210102_P01_WALL-PANEL-ASSY-SIDE-LOWER-RH_CAD (Autodesk Fusion 360 design; units mm, degrees)
part number: 2026-11-01-01-12-47-745
description: WALL - PANEL FRAME - SIDE LOWER - RH | Vách phải - khung dưới | P01
part number: 211102
description: WALL - SKIN - SIDE LOWER - RH | Vách phải - tấm ốp alu dưới | P01
part number: 211302
description: WALL - CAVITY FILL - SIDE LOWER - RH | Vách phải - bông PET dưới | P01
part number: 211502
description: HARDWARE - STOP WASHER - Ø10.5 X Ø20 X 1.5 - AL | Long đen chặn nhôm | P01
part number: 831002
description: HARDWARE - RIVET NUT - M6 - SHEREX CAH3-610-4.2 | Tán rút M6 | P01
part number: 838003
description: HARDWARE - LOCATING SPIGOT - M6 X Ø8 - STAINLESS | Chốt định vị Ø8 | P01
part number: 831001
Autodesk Fusion 360 part; units mm, degrees
(part 1 of 2)
ref_plane "WorkPlane1" through (0, 0, 112.26) normal (0, 0, 1) x (1, 0, 0) in component "211102 WALL - PANEL FRAME - SIDE LOWER - RH"
sketch "SKETCH - RAIL - BOTTOM TUBE" plane through (0, 0, 112.26) normal (0, 0, 1) x (1, 0, 0) in component "211102 WALL - PANEL FRAME - SIDE LOWER - RH"
  line L0 (1204, -642.74) -> (1244, -642.74)
  line L1 (1244, -642.74) -> (1244, 847)
  line L2 (1244, 847) -> (1204, 847)
  line L3 (1204, 847) -> (1204, -642.74)
  dimension "d167" = 40
  dimension "d168" = 1489.74
  dimension "d169" = 1204
  dimension "d170" = 642.74
  constraint horizontal L0
  constraint vertical L1
  constraint horizontal L2
  constraint vertical L3
  measures "d167" horizontal distance of L0.start L0.end
  measures "d168" vertical distance of L0.start L2.end
  measures "d169" horizontal distance of origin L0.start
  measures "d170" vertical distance of origin L0.start
extrude "EXTRUDE - RAIL - BOTTOM TUBE" add sketch "SKETCH - RAIL - BOTTOM TUBE" along normal blind 20 makes body 1 in component "211102 WALL - PANEL FRAME - SIDE LOWER - RH"
ref_plane "WorkPlane2" through (0, 0, 113.46) normal (0, 0, 1) x (1, 0, 0) in component "211102 WALL - PANEL FRAME - SIDE LOWER - RH"
sketch "SKETCH - RAIL - BOTTOM BORE" plane through (0, 0, 113.46) normal (0, 0, 1) x (1, 0, 0) in component "211102 WALL - PANEL FRAME - SIDE LOWER - RH"
  line L0 (1205.2, -642.74) -> (1242.8, -642.74)
  line L1 (1242.8, -642.74) -> (1242.8, 847)
  line L2 (1242.8, 847) -> (1205.2, 847)
  line L3 (1205.2, 847) -> (1205.2, -642.74)
  dimension "d175" = 37.6
  dimension "d176" = 1489.74
  dimension "d177" = 1205.2
  dimension "d178" = 642.74
  constraint horizontal L0
  constraint vertical L1
  constraint horizontal L2
  constraint vertical L3
  measures "d175" horizontal distance of L0.start L0.end
  measures "d176" vertical distance of L0.start L2.end
  measures "d177" horizontal distance of origin L0.start
  measures "d178" vertical distance of origin L0.start
extrude "CUT - RAIL - BOTTOM BORE" cut sketch "SKETCH - RAIL - BOTTOM BORE" along normal blind 17.6 bodies 1 in component "211102 WALL - PANEL FRAME - SIDE LOWER - RH"
ref_plane "WorkPlane3" through (0, 0, 1235) normal (0, 0, 1) x (1, 0, 0) in component "211102 WALL - PANEL FRAME - SIDE LOWER - RH"
sketch "SKETCH - RAIL - TOP TUBE" plane through (0, 0, 1235) normal (0, 0, 1) x (1, 0, 0) in component "211102 WALL - PANEL FRAME - SIDE LOWER - RH"
  line L0 (1204, -642.74) -> (1244, -642.74)
  line L1 (1244, -642.74) -> (1244, 847)
  line L2 (1244, 847) -> (1204, 847)
  line L3 (1204, 847) -> (1204, -642.74)
  dimension "d183" = 40
  dimension "d184" = 1489.74
  dimension "d185" = 1204
  dimension "d186" = 642.74
  constraint horizontal L0
  constraint vertical L1
  constraint horizontal L2
  constraint vertical L3
  measures "d183" horizontal distance of L0.start L0.end
  measures "d184" vertical distance of L0.start L2.end
  measures "d185" horizontal distance of origin L0.start
  measures "d186" vertical distance of origin L0.start
extrude "EXTRUDE - RAIL - TOP TUBE" add sketch "SKETCH - RAIL - TOP TUBE" along normal blind 20 separate body makes body 2 in component "211102 WALL - PANEL FRAME - SIDE LOWER - RH"
ref_plane "WorkPlane4" through (0, 0, 1236.2) normal (0, 0, 1) x (1, 0, 0) in component "211102 WALL - PANEL FRAME - SIDE LOWER - RH"
sketch "SKETCH - RAIL - TOP BORE" plane through (0, 0, 1236.2) normal (0, 0, 1) x (1, 0, 0) in component "211102 WALL - PANEL FRAME - SIDE LOWER - RH"
  line L0 (1205.2, -642.74) -> (1242.8, -642.74)
  line L1 (1242.8, -642.74) -> (1242.8, 847)
  line L2 (1242.8, 847) -> (1205.2, 847)
  line L3 (1205.2, 847) -> (1205.2, -642.74)
  dimension "d191" = 37.6
  dimension "d192" = 1489.74
  dimension "d193" = 1205.2
  dimension "d194" = 642.74
  constraint horizontal L0
  constraint vertical L1
  constraint horizontal L2
  constraint vertical L3
  measures "d191" horizontal distance of L0.start L0.end
  measures "d192" vertical distance of L0.start L2.end
  measures "d193" horizontal distance of origin L0.start
  measures "d194" vertical distance of origin L0.start
extrude "CUT - RAIL - TOP BORE" cut sketch "SKETCH - RAIL - TOP BORE" along normal blind 17.6 bodies 2 in component "211102 WALL - PANEL FRAME - SIDE LOWER - RH"
ref_plane "WorkPlane5" through (0, 0, 132.26) normal (0, 0, 1) x (1, 0, 0) in component "211102 WALL - PANEL FRAME - SIDE LOWER - RH"
sketch "SKETCH - STILE - FRONT TUBE" plane through (0, 0, 132.26) normal (0, 0, 1) x (1, 0, 0) in component "211102 WALL - PANEL FRAME - SIDE LOWER - RH"
  line L0 (1204, -642.74) -> (1244, -642.74)
  line L1 (1244, -642.74) -> (1244, -622.74)
  line L2 (1244, -622.74) -> (1204, -622.74)
  line L3 (1204, -622.74) -> (1204, -642.74)
  dimension "d199" = 40
  dimension "d200" = 20
  dimension "d201" = 1204
  dimension "d202" = 642.74
  constraint horizontal L0
  constraint vertical L1
  constraint horizontal L2
  constraint vertical L3
  measures "d199" horizontal distance of L0.start L0.end
  measures "d200" vertical distance of L0.start L2.end
  measures "d201" horizontal distance of origin L0.start
  measures "d202" vertical distance of origin L0.start
extrude "EXTRUDE - STILE - FRONT TUBE" add sketch "SKETCH - STILE - FRONT TUBE" along normal blind 1102.74 separate body makes body 3 in component "211102 WALL - PANEL FRAME - SIDE LOWER - RH"
ref_plane "WorkPlane6" through (0, 0, 132.26) normal (0, 0, 1) x (1, 0, 0) in component "211102 WALL - PANEL FRAME - SIDE LOWER - RH"
sketch "SKETCH - STILE - FRONT BORE" plane through (0, 0, 132.26) normal (0, 0, 1) x (1, 0, 0) in component "211102 WALL - PANEL FRAME - SIDE LOWER - RH"
  line L0 (1205.2, -641.54) -> (1242.8, -641.54)
  line L1 (1242.8, -641.54) -> (1242.8, -623.94)
  line L2 (1242.8, -623.94) -> (1205.2, -623.94)
  line L3 (1205.2, -623.94) -> (1205.2, -641.54)
  dimension "d207" = 37.6
  dimension "d208" = 17.6
  dimension "d209" = 1205.2
  dimension "d210" = 641.54
  constraint horizontal L0
  constraint vertical L1
  constraint horizontal L2
  constraint vertical L3
  measures "d207" horizontal distance of L0.start L0.end
  measures "d208" vertical distance of L0.start L2.end
  measures "d209" horizontal distance of origin L0.start
  measures "d210" vertical distance of origin L0.start
extrude "CUT - STILE - FRONT BORE" cut sketch "SKETCH - STILE - FRONT BORE" along normal blind 1102.74 bodies 3 in component "211102 WALL - PANEL FRAME - SIDE LOWER - RH"
ref_plane "WorkPlane7" through (0, 0, 132.26) normal (0, 0, 1) x (1, 0, 0) in component "211102 WALL - PANEL FRAME - SIDE LOWER - RH"
sketch "SKETCH - STILE - BACK TUBE" plane through (0, 0, 132.26) normal (0, 0, 1) x (1, 0, 0) in component "211102 WALL - PANEL FRAME - SIDE LOWER - RH"
  line L0 (1204, 807) -> (1244, 807)
  line L1 (1244, 807) -> (1244, 847)
  line L2 (1244, 847) -> (1204, 847)
  line L3 (1204, 847) -> (1204, 807)
  dimension "d215" = 40
  dimension "d216" = 40
  dimension "d217" = 1204
  dimension "d218" = 807
  constraint horizontal L0
  constraint vertical L1
  constraint horizontal L2
  constraint vertical L3
  measures "d215" horizontal distance of L0.start L0.end
  measures "d216" vertical distance of L0.start L2.end
  measures "d217" horizontal distance of origin L0.start
  measures "d218" vertical distance of origin L0.start
extrude "EXTRUDE - STILE - BACK TUBE" add sketch "SKETCH - STILE - BACK TUBE" along normal blind 1102.74 separate body makes body 4 in component "211102 WALL - PANEL FRAME - SIDE LOWER - RH"
ref_plane "WorkPlane8" through (0, 0, 132.26) normal (0, 0, 1) x (1, 0, 0) in component "211102 WALL - PANEL FRAME - SIDE LOWER - RH"
sketch "SKETCH - STILE - BACK BORE" plane through (0, 0, 132.26) normal (0, 0, 1) x (1, 0, 0) in component "211102 WALL - PANEL FRAME - SIDE LOWER - RH"
  line L0 (1205.2, 808.2) -> (1242.8, 808.2)
  line L1 (1242.8, 808.2) -> (1242.8, 845.8)
  line L2 (1242.8, 845.8) -> (1205.2, 845.8)
  line L3 (1205.2, 845.8) -> (1205.2, 808.2)
  dimension "d223" = 37.6
  dimension "d224" = 37.6
  dimension "d225" = 1205.2
  dimension "d226" = 808.2
  constraint horizontal L0
  constraint vertical L1
  constraint horizontal L2
  constraint vertical L3
  measures "d223" horizontal distance of L0.start L0.end
  measures "d224" vertical distance of L0.start L2.end
  measures "d225" horizontal distance of origin L0.start
  measures "d226" vertical distance of origin L0.start
extrude "CUT - STILE - BACK BORE" cut sketch "SKETCH - STILE - BACK BORE" along normal blind 1102.74 bodies 4 in component "211102 WALL - PANEL FRAME - SIDE LOWER - RH"
ref_plane "WorkPlane9" through (0, 0, 132.26) normal (0, 0, 1) x (1, 0, 0) in component "211102 WALL - PANEL FRAME - SIDE LOWER - RH"
sketch "SKETCH - STILE - MID 1 TUBE" plane through (0, 0, 132.26) normal (0, 0, 1) x (1, 0, 0) in component "211102 WALL - PANEL FRAME - SIDE LOWER - RH"
  line L0 (1204, -277.805) -> (1244, -277.805)
  line L1 (1244, -277.805) -> (1244, -257.805)
  line L2 (1244, -257.805) -> (1204, -257.805)
  line L3 (1204, -257.805) -> (1204, -277.805)
  dimension "d231" = 40
  dimension "d232" = 20
  dimension "d233" = 1204
  dimension "d234" = 277.805
  constraint horizontal L0
  constraint vertical L1
  constraint horizontal L2
  constraint vertical L3
  measures "d231" horizontal distance of L0.start L0.end
  measures "d232" vertical distance of L0.start L2.end
  measures "d233" horizontal distance of origin L0.start
  measures "d234" vertical distance of origin L0.start
extrude "EXTRUDE - STILE - MID 1 TUBE" add sketch "SKETCH - STILE - MID 1 TUBE" along normal blind 1102.74 separate body makes body 5 in component "211102 WALL - PANEL FRAME - SIDE LOWER - RH"
ref_plane "WorkPlane10" through (0, 0, 132.26) normal (0, 0, 1) x (1, 0, 0) in component "211102 WALL - PANEL FRAME - SIDE LOWER - RH"
sketch "SKETCH - STILE - MID 1 BORE" plane through (0, 0, 132.26) normal (0, 0, 1) x (1, 0, 0) in component "211102 WALL - PANEL FRAME - SIDE LOWER - RH"
  line L0 (1205, -276.805) -> (1243, -276.805)
  line L1 (1243, -276.805) -> (1243, -258.805)
  line L2 (1243, -258.805) -> (1205, -258.805)
  line L3 (1205, -258.805) -> (1205, -276.805)
  dimension "d239" = 38
  dimension "d240" = 18
  dimension "d241" = 1205
  dimension "d242" = 276.805
  constraint horizontal L0
  constraint vertical L1
  constraint horizontal L2
  constraint vertical L3
  measures "d239" horizontal distance of L0.start L0.end
  measures "d240" vertical distance of L0.start L2.end
  measures "d241" horizontal distance of origin L0.start
  measures "d242" vertical distance of origin L0.start
extrude "CUT - STILE - MID 1 BORE" cut sketch "SKETCH - STILE - MID 1 BORE" along normal blind 1102.74 bodies 5 in component "211102 WALL - PANEL FRAME - SIDE LOWER - RH"
pattern_linear "PATTERN - STILES - MID" count 3 spacing 364.935 along (0, 1, 0) of bodies 5 makes body 6 at (1230.6667, 107.13, 499.84) makes body 7 at (1230.6667, 472.065, 499.84) in component "211102 WALL - PANEL FRAME - SIDE LOWER - RH"
ref_plane "WorkPlane1" through (0, 0, 112.26) normal (0, 0, 1) x (1, 0, 0) in component "211302 WALL - SKIN - SIDE LOWER - RH"
sketch "SKETCH - SKIN PLATE" plane through (0, 0, 112.26) normal (0, 0, 1) x (1, 0, 0) in component "211302 WALL - SKIN - SIDE LOWER - RH"
  line L0 (1247, -642.74) -> (1250, -642.74)
  line L1 (1250, -642.74) -> (1250, 850)
  line L2 (1250, 850) -> (1247, 850)
  line L3 (1247, 850) -> (1247, -642.74)
  dimension "d251" = 3
  dimension "d252" = 1492.74
  dimension "d253" = 1247
  dimension "d254" = 642.74
  constraint horizontal L0
  constraint vertical L1
  constraint horizontal L2
  constraint vertical L3
  measures "d251" horizontal distance of L0.start L0.end
  measures "d252" vertical distance of L0.start L2.end
  measures "d253" horizontal distance of origin L0.start
  measures "d254" vertical distance of origin L0.start
extrude "EXTRUDE - SKIN PLATE" add sketch "SKETCH - SKIN PLATE" along normal blind 1142.74 separate body makes body 8 in component "211302 WALL - SKIN - SIDE LOWER - RH"
ref_plane "WorkPlane2" through (0, 0, 112.26) normal (0, 0, 1) x (1, 0, 0) in component "211302 WALL - SKIN - SIDE LOWER - RH"
sketch "SKETCH - SKIN BACK RETURN" plane through (0, 0, 112.26) normal (0, 0, 1) x (1, 0, 0) in component "211302 WALL - SKIN - SIDE LOWER - RH"
  line L0 (1204, 847) -> (1247, 847)
  line L1 (1247, 847) -> (1247, 850)
  line L2 (1247, 850) -> (1204, 850)
  line L3 (1204, 850) -> (1204, 847)
  dimension "d259" = 43
  dimension "d260" = 3
  dimension "d261" = 1204
  dimension "d262" = 847
  constraint horizontal L0
  constraint vertical L1
  constraint horizontal L2
  constraint vertical L3
  measures "d259" horizontal distance of L0.start L0.end
  measures "d260" vertical distance of L0.start L2.end
  measures "d261" horizontal distance of origin L0.start
  measures "d262" vertical distance of origin L0.start
extrude "JOIN - SKIN BACK RETURN" add sketch "SKETCH - SKIN BACK RETURN" along normal blind 1142.74 bodies 8 in component "211302 WALL - SKIN - SIDE LOWER - RH"
ref_plane "WorkPlane1" through (0, 0, 132.26) normal (0, 0, 1) x (1, 0, 0) in component "211502 WALL - CAVITY FILL - SIDE LOWER - RH"
sketch "SKETCH - FILL BAY 1" plane through (0, 0, 132.26) normal (0, 0, 1) x (1, 0, 0) in component "211502 WALL - CAVITY FILL - SIDE LOWER - RH"
  line L0 (1204, -622.74) -> (1244, -622.74)
  line L1 (1244, -622.74) -> (1244, -277.805)
  line L2 (1244, -277.805) -> (1204, -277.805)
  line L3 (1204, -277.805) -> (1204, -622.74)
  dimension "d267" = 40
  dimension "d268" = 344.935
  dimension "d269" = 1204
  dimension "d270" = 622.74
  constraint horizontal L0
  constraint vertical L1
  constraint horizontal L2
  constraint vertical L3
  measures "d267" horizontal distance of L0.start L0.end
  measures "d268" vertical distance of L0.start L2.end
  measures "d269" horizontal distance of origin L0.start
  measures "d270" vertical distance of origin L0.start
extrude "EXTRUDE - FILL BAY 1" add sketch "SKETCH - FILL BAY 1" along normal blind 1102.74 separate body makes body 9 in component "211502 WALL - CAVITY FILL - SIDE LOWER - RH"
pattern_linear "PATTERN - FILL BAYS" count 3 spacing 364.935 along (0, 1, 0) of bodies 9 makes body 10 at (1204, -27.8483, 499.84) makes body 11 at (1204, 337.0867, 499.84) in component "211502 WALL - CAVITY FILL - SIDE LOWER - RH"
ref_plane "WorkPlane2" through (0, 0, 132.26) normal (0, 0, 1) x (1, 0, 0) in component "211502 WALL - CAVITY FILL - SIDE LOWER - RH"
sketch "SKETCH - FILL BAY LAST" plane through (0, 0, 132.26) normal (0, 0, 1) x (1, 0, 0) in component "211502 WALL - CAVITY FILL - SIDE LOWER - RH"
  line L0 (1204, 472.065) -> (1244, 472.065)
  line L1 (1244, 472.065) -> (1244, 807)
  line L2 (1244, 807) -> (1204, 807)
  line L3 (1204, 807) -> (1204, 472.065)
  dimension "d279" = 40
  dimension "d280" = 334.935
  dimension "d281" = 1204
  dimension "d282" = 472.065
  constraint horizontal L0
  constraint vertical L1
  constraint horizontal L2
  constraint vertical L3
  measures "d279" horizontal distance of L0.start L0.end
  measures "d280" vertical distance of L0.start L2.end
  measures "d281" horizontal distance of origin L0.start
  measures "d282" vertical distance of origin L0.start
extrude "EXTRUDE - FILL BAY LAST" add sketch "SKETCH - FILL BAY LAST" along normal blind 1102.74 separate body makes body 12 in component "211502 WALL - CAVITY FILL - SIDE LOWER - RH"
ref_plane "WorkPlane3" through (0, 0, 132.26) normal (0, 0, 1) x (1, 0, 0) in component "211502 WALL - CAVITY FILL - SIDE LOWER - RH"
sketch "SKETCH - FILL POCKET BOTTOM BOLT 1" plane through (0, 0, 132.26) normal (0, 0, 1) x (1, 0, 0) in component "211502 WALL - CAVITY FILL - SIDE LOWER - RH"
  line L0 (1204, -452.74) -> (1244, -452.74)
  line L1 (1244, -452.74) -> (1244, -392.74)
  line L2 (1244, -392.74) -> (1204, -392.74)
  line L3 (1204, -392.74) -> (1204, -452.74)
  dimension "d287" = 40
  dimension "d288" = 60
  dimension "d289" = 1204
  dimension "d290" = 452.74
  constraint horizontal L0
  constraint vertical L1
  constraint horizontal L2
  constraint vertical L3
  measures "d287" horizontal distance of L0.start L0.end
  measures "d288" vertical distance of L0.start L2.end
  measures "d289" horizontal distance of origin L0.start
  measures "d290" vertical distance of origin L0.start
extrude "CUT - FILL POCKET BOTTOM BOLT 1" cut sketch "SKETCH - FILL POCKET BOTTOM BOLT 1" along normal blind 60 bodies 9 in component "211502 WALL - CAVITY FILL - SIDE LOWER - RH"
ref_plane "WorkPlane4" through (0, 0, 132.26) normal (0, 0, 1) x (1, 0, 0) in component "211502 WALL - CAVITY FILL - SIDE LOWER - RH"
sketch "SKETCH - FILL POCKET BOTTOM BOLT 2" plane through (0, 0, 132.26) normal (0, 0, 1) x (1, 0, 0) in component "211502 WALL - CAVITY FILL - SIDE LOWER - RH"
  line L0 (1204, -101.8267) -> (1244, -101.8267)
  line L1 (1244, -101.8267) -> (1244, -41.8267)
  line L2 (1244, -41.8267) -> (1204, -41.8267)
  line L3 (1204, -41.8267) -> (1204, -101.8267)
  dimension "d295" = 40
  dimension "d296" = 60
  dimension "d297" = 1204
  dimension "d298" = 101.8267
  constraint horizontal L0
  constraint vertical L1
  constraint horizontal L2
  constraint vertical L3
  measures "d295" horizontal distance of L0.start L0.end
  measures "d296" vertical distance of L0.start L2.end
  measures "d297" horizontal distance of origin L0.start
  measures "d298" vertical distance of origin L0.start
extrude "CUT - FILL POCKET BOTTOM BOLT 2" cut sketch "SKETCH - FILL POCKET BOTTOM BOLT 2" along normal blind 60 bodies 10 in component "211502 WALL - CAVITY FILL - SIDE LOWER - RH"
ref_plane "WorkPlane5" through (0, 0, 132.26) normal (0, 0, 1) x (1, 0, 0) in component "211502 WALL - CAVITY FILL - SIDE LOWER - RH"
sketch "SKETCH - FILL POCKET BOTTOM BOLT 3" plane through (0, 0, 132.26) normal (0, 0, 1) x (1, 0, 0) in component "211502 WALL - CAVITY FILL - SIDE LOWER - RH"
  line L0 (1204, 249.0867) -> (1244, 249.0867)
  line L1 (1244, 249.0867) -> (1244, 309.0867)
  line L2 (1244, 309.0867) -> (1204, 309.0867)
  line L3 (1204, 309.0867) -> (1204, 249.0867)
  dimension "d303" = 40
  dimension "d304" = 60
  dimension "d305" = 1204
  dimension "d306" = 249.0867
  constraint horizontal L0
  constraint vertical L1
  constraint horizontal L2
  constraint vertical L3
  measures "d303" horizontal distance of L0.start L0.end
  measures "d304" vertical distance of L0.start L2.end
  measures "d305" horizontal distance of origin L0.start
  measures "d306" vertical distance of origin L0.start
extrude "CUT - FILL POCKET BOTTOM BOLT 3" cut sketch "SKETCH - FILL POCKET BOTTOM BOLT 3" along normal blind 60 bodies 11 in component "211502 WALL - CAVITY FILL - SIDE LOWER - RH"
ref_plane "WorkPlane6" through (0, 0, 132.26) normal (0, 0, 1) x (1, 0, 0) in component "211502 WALL - CAVITY FILL - SIDE LOWER - RH"
sketch "SKETCH - FILL POCKET BOTTOM BOLT 4" plane through (0, 0, 132.26) normal (0, 0, 1) x (1, 0, 0) in component "211502 WALL - CAVITY FILL - SIDE LOWER - RH"
  line L0 (1204, 600) -> (1244, 600)
  line L1 (1244, 600) -> (1244, 660)
  line L2 (1244, 660) -> (1204, 660)
  line L3 (1204, 660) -> (1204, 600)
  dimension "d311" = 40
  dimension "d312" = 60
  dimension "d313" = 1204
  dimension "d314" = 600
  constraint horizontal L0
  constraint vertical L1
  constraint horizontal L2
  constraint vertical L3
  measures "d311" horizontal distance of L0.start L0.end
  measures "d312" vertical distance of L0.start L2.end
  measures "d313" horizontal distance of origin L0.start
  measures "d314" vertical distance of origin L0.start
extrude "CUT - FILL POCKET BOTTOM BOLT 4" cut sketch "SKETCH - FILL POCKET BOTTOM BOLT 4" along normal blind 60 bodies 12 in component "211502 WALL - CAVITY FILL - SIDE LOWER - RH"
ref_plane "WorkPlane7" through (0, 0, 302.26) normal (0, 0, 1) x (1, 0, 0) in component "211502 WALL - CAVITY FILL - SIDE LOWER - RH"
sketch "SKETCH - FILL POCKET DECOR BOLT 1" plane through (0, 0, 302.26) normal (0, 0, 1) x (1, 0, 0) in component "211502 WALL - CAVITY FILL - SIDE LOWER - RH"
  line L0 (1204, -622.74) -> (1244, -622.74)
  line L1 (1244, -622.74) -> (1244, -562.74)
  line L2 (1244, -562.74) -> (1204, -562.74)
  line L3 (1204, -562.74) -> (1204, -622.74)
  dimension "d319" = 40
  dimension "d320" = 60
  dimension "d321" = 1204
  dimension "d322" = 622.74
  constraint horizontal L0
  constraint vertical L1
  constraint horizontal L2
  constraint vertical L3
  measures "d319" horizontal distance of L0.start L0.end
  measures "d320" vertical distance of L0.start L2.end
  measures "d321" horizontal distance of origin L0.start
  measures "d322" vertical distance of origin L0.start
extrude "CUT - FILL POCKET DECOR BOLT 1" cut sketch "SKETCH - FILL POCKET DECOR BOLT 1" along normal blind 60 bodies 9 in component "211502 WALL - CAVITY FILL - SIDE LOWER - RH"
ref_plane "WorkPlane8" through (0, 0, 653.63) normal (0, 0, 1) x (1, 0, 0) in component "211502 WALL - CAVITY FILL - SIDE LOWER - RH"
sketch "SKETCH - FILL POCKET DECOR BOLT 2" plane through (0, 0, 653.63) normal (0, 0, 1) x (1, 0, 0) in component "211502 WALL - CAVITY FILL - SIDE LOWER - RH"
  line L0 (1204, -622.74) -> (1244, -622.74)
  line L1 (1244, -622.74) -> (1244, -562.74)
  line L2 (1244, -562.74) -> (1204, -562.74)
  line L3 (1204, -562.74) -> (1204, -622.74)
  dimension "d327" = 40
  dimension "d328" = 60
  dimension "d329" = 1204
  dimension "d330" = 622.74
  constraint horizontal L0
  constraint vertical L1
  constraint horizontal L2
  constraint vertical L3
  measures "d327" horizontal distance of L0.start L0.end
  measures "d328" vertical distance of L0.start L2.end
  measures "d329" horizontal distance of origin L0.start
  measures "d330" vertical distance of origin L0.start
extrude "CUT - FILL POCKET DECOR BOLT 2" cut sketch "SKETCH - FILL POCKET DECOR BOLT 2" along normal blind 60 bodies 9 in component "211502 WALL - CAVITY FILL - SIDE LOWER - RH"
ref_plane "WorkPlane9" through (0, 0, 1005) normal (0, 0, 1) x (1, 0, 0) in component "211502 WALL - CAVITY FILL - SIDE LOWER - RH"
sketch "SKETCH - FILL POCKET DECOR BOLT 3" plane through (0, 0, 1005) normal (0, 0, 1) x (1, 0, 0) in component "211502 WALL - CAVITY FILL - SIDE LOWER - RH"
  line L0 (1204, -622.74) -> (1244, -622.74)
  line L1 (1244, -622.74) -> (1244, -562.74)
  line L2 (1244, -562.74) -> (1204, -562.74)
  line L3 (1204, -562.74) -> (1204, -622.74)
  dimension "d335" = 40
  dimension "d336" = 60
  dimension "d337" = 1204
  dimension "d338" = 622.74
  constraint horizontal L0
  constraint vertical L1
  constraint horizontal L2
  constraint vertical L3
  measures "d335" horizontal distance of L0.start L0.end
  measures "d336" vertical distance of L0.start L2.end
  measures "d337" horizontal distance of origin L0.start
  measures "d338" vertical distance of origin L0.start
extrude "CUT - FILL POCKET DECOR BOLT 3" cut sketch "SKETCH - FILL POCKET DECOR BOLT 3" along normal blind 60 bodies 9 in component "211502 WALL - CAVITY FILL - SIDE LOWER - RH"
ref_plane "WorkPlane11" through (0, 0, 112.26) normal (0, 0, 1) x (1, 0, 0) in component "211102 WALL - PANEL FRAME - SIDE LOWER - RH"
sketch "HOLE CENTRE - BOTTOM RAIL BOLT CLEARANCE 1" plane through (0, 0, 112.26) normal (0, 0, 1) x (1, 0, 0) in component "211102 WALL - PANEL FRAME - SIDE LOWER - RH"
  point P0 (1224, -422.74)
  dimension "d343" = 1224
  dimension "d344" = 422.74
  measures "d343" horizontal distance of origin P0
  measures "d344" vertical distance of origin P0
hole "HOLE - BOTTOM RAIL BOLT CLEARANCE 1" at (1224, -422.74, 112.26) direction (0, 0, 1) diameter 7 depth 1.2 tip angle 118 bodies 1 in component "211102 WALL - PANEL FRAME - SIDE LOWER - RH"
ref_plane "WorkPlane12" through (0, 0, 132.26) normal (0, 0, 1) x (1, 0, 0) in component "211102 WALL - PANEL FRAME - SIDE LOWER - RH"
sketch "HOLE CENTRE - BOTTOM RAIL KEY ACCESS 1" plane through (0, 0, 132.26) normal (0, 0, 1) x (1, 0, 0) in component "211102 WALL - PANEL FRAME - SIDE LOWER - RH"
  point P0 (1224, -422.74)
  dimension "d350" = 1224
  dimension "d351" = 422.74
  measures "d350" horizontal distance of origin P0
  measures "d351" vertical distance of origin P0
hole "HOLE - BOTTOM RAIL KEY ACCESS 1" at (1224, -422.74, 132.26) direction (0, 0, -1) diameter 19 depth 1.2 tip angle 118 bodies 1 in component "211102 WALL - PANEL FRAME - SIDE LOWER - RH"
pattern_linear "PATTERN - BOTTOM RAIL BOLT HOLES" count 4 spacing 350.9133 along (0, 1, 0) of "HOLE - BOTTOM RAIL BOLT CLEARANCE 1", "HOLE - BOTTOM RAIL KEY ACCESS 1" in component "211102 WALL - PANEL FRAME - SIDE LOWER - RH"
ref_plane "WorkPlane13" through (0, 0, 112.26) normal (0, 0, 1) x (1, 0, 0) in component "211102 WALL - PANEL FRAME - SIDE LOWER - RH"
sketch "HOLE CENTRE - BOTTOM RAIL SPIGOT ROUND" plane through (0, 0, 112.26) normal (0, 0, 1) x (1, 0, 0) in component "211102 WALL - PANEL FRAME - SIDE LOWER - RH"
  point P0 (1224, -542.74)
  dimension "d361" = 1224
  dimension "d362" = 542.74
  measures "d361" horizontal distance of origin P0
  measures "d362" vertical distance of origin P0
hole "HOLE - BOTTOM RAIL SPIGOT ROUND" at (1224, -542.74, 112.26) direction (0, 0, 1) diameter 8.5 depth 1.2 tip angle 118 bodies 1 in component "211102 WALL - PANEL FRAME - SIDE LOWER - RH"
ref_plane "WorkPlane14" through (0, 0, 112.26) normal (0, 0, 1) x (1, 0, 0) in component "211102 WALL - PANEL FRAME - SIDE LOWER - RH"
sketch "SKETCH - BOTTOM RAIL SPIGOT SLOT" plane through (0, 0, 112.26) normal (0, 0, 1) x (1, 0, 0) in component "211102 WALL - PANEL FRAME - SIDE LOWER - RH"
  line L0 (1221.25, 745.75) -> (1226.75, 745.75)
  line L1 (1226.75, 745.75) -> (1226.75, 754.25)
  line L2 (1226.75, 754.25) -> (1221.25, 754.25)
  line L3 (1221.25, 754.25) -> (1221.25, 745.75)
  dimension "d368" = 5.5
  dimension "d369" = 8.5
  dimension "d370" = 1221.25
  dimension "d371" = 745.75
  constraint horizontal L0
  constraint vertical L1
  constraint horizontal L2
  constraint vertical L3
  measures "d368" horizontal distance of L0.start L0.end
  measures "d369" vertical distance of L0.start L2.end
  measures "d370" horizontal distance of origin L0.start
  measures "d371" vertical distance of origin L0.start
extrude "CUT - BOTTOM RAIL SPIGOT SLOT" cut sketch "SKETCH - BOTTOM RAIL SPIGOT SLOT" along normal blind 1.2 bodies 1 in component "211102 WALL - PANEL FRAME - SIDE LOWER - RH"
ref_plane "WorkPlane15" through (0, 0, 112.26) normal (0, 0, 1) x (1, 0, 0) in component "211102 WALL - PANEL FRAME - SIDE LOWER - RH"
sketch "HOLE CENTRE - BOTTOM RAIL SPIGOT SLOT END 1" plane through (0, 0, 112.26) normal (0, 0, 1) x (1, 0, 0) in component "211102 WALL - PANEL FRAME - SIDE LOWER - RH"
  point P0 (1221.25, 750)
  dimension "d376" = 1221.25
  dimension "d377" = 750
  measures "d376" horizontal distance of origin P0
  measures "d377" vertical distance of origin P0
hole "HOLE - BOTTOM RAIL SPIGOT SLOT END 1" at (1221.25, 750, 112.26) direction (0, 0, 1) diameter 8.5 depth 1.2 tip angle 118 bodies 1 in component "211102 WALL - PANEL FRAME - SIDE LOWER - RH"
ref_plane "WorkPlane16" through (0, 0, 112.26) normal (0, 0, 1) x (1, 0, 0) in component "211102 WALL - PANEL FRAME - SIDE LOWER - RH"
sketch "HOLE CENTRE - BOTTOM RAIL SPIGOT SLOT END 2" plane through (0, 0, 112.26) normal (0, 0, 1) x (1, 0, 0) in component "211102 WALL - PANEL FRAME - SIDE LOWER - RH"
  point P0 (1226.75, 750)
  dimension "d383" = 1226.75
  dimension "d384" = 750
  measures "d383" horizontal distance of origin P0
  measures "d384" vertical distance of origin P0
hole "HOLE - BOTTOM RAIL SPIGOT SLOT END 2" at (1226.75, 750, 112.26) direction (0, 0, 1) diameter 8.5 depth 1.2 tip angle 118 bodies 1 in component "211102 WALL - PANEL FRAME - SIDE LOWER - RH"
ref_plane "WorkPlane17" through (0, 0, 1255) normal (0, 0, 1) x (1, 0, 0) in component "211102 WALL - PANEL FRAME - SIDE LOWER - RH"
sketch "HOLE CENTRE - TOP RAIL RIVNUT 1" plane through (0, 0, 1255) normal (0, 0, 1) x (1, 0, 0) in component "211102 WALL - PANEL FRAME - SIDE LOWER - RH"
  point P0 (1224, -422.74)
  dimension "d390" = 1224
  dimension "d391" = 422.74
  measures "d390" horizontal distance of origin P0
  measures "d391" vertical distance of origin P0
hole "HOLE - TOP RAIL RIVNUT 1" at (1224, -422.74, 1255) direction (0, 0, -1) diameter 9.53 depth 1.2 tip angle 118 bodies 2 in component "211102 WALL - PANEL FRAME - SIDE LOWER - RH"
pattern_linear "PATTERN - TOP RAIL RIVNUTS" count 4 spacing 350.9133 along (0, 1, 0) of "HOLE - TOP RAIL RIVNUT 1" in component "211102 WALL - PANEL FRAME - SIDE LOWER - RH"
ref_plane "WorkPlane18" through (0, 0, 1255) normal (0, 0, 1) x (1, 0, 0) in component "211102 WALL - PANEL FRAME - SIDE LOWER - RH"
sketch "HOLE CENTRE - TOP RAIL SPIGOT RIVNUT FRONT" plane through (0, 0, 1255) normal (0, 0, 1) x (1, 0, 0) in component "211102 WALL - PANEL FRAME - SIDE LOWER - RH"
  point P0 (1224, -542.74)
  dimension "d401" = 1224
  dimension "d402" = 542.74
  measures "d401" horizontal distance of origin P0
  measures "d402" vertical distance of origin P0
hole "HOLE - TOP RAIL SPIGOT RIVNUT FRONT" at (1224, -542.74, 1255) direction (0, 0, -1) diameter 9.53 depth 1.2 tip angle 118 bodies 2 in component "211102 WALL - PANEL FRAME - SIDE LOWER - RH"
ref_plane "WorkPlane19" through (0, 0, 1255) normal (0, 0, 1) x (1, 0, 0) in component "211102 WALL - PANEL FRAME - SIDE LOWER - RH"
sketch "HOLE CENTRE - TOP RAIL SPIGOT RIVNUT BACK" plane through (0, 0, 1255) normal (0, 0, 1) x (1, 0, 0) in component "211102 WALL - PANEL FRAME - SIDE LOWER - RH"
  point P0 (1224, 750)
  dimension "d408" = 1224
  dimension "d409" = 750
  measures "d408" horizontal distance of origin P0
  measures "d409" vertical distance of origin P0
hole "HOLE - TOP RAIL SPIGOT RIVNUT BACK" at (1224, 750, 1255) direction (0, 0, -1) diameter 9.53 depth 1.2 tip angle 118 bodies 2 in component "211102 WALL - PANEL FRAME - SIDE LOWER - RH"
ref_plane "WorkPlane20" through (0, -642.74, 0) normal (0, 1, 0) x (0, 0, 1) in component "211102 WALL - PANEL FRAME - SIDE LOWER - RH"
sketch "HOLE CENTRE - FRONT STILE BOLT CLEARANCE 1" plane through (0, -642.74, 0) normal (0, 1, 0) x (1, 0, 0) in component "211102 WALL - PANEL FRAME - SIDE LOWER - RH"
  point P0 (1224, -332.26)
  dimension "d415" = 1224
  dimension "d416" = 332.26
  measures "d415" horizontal distance of origin P0
  measures "d416" vertical distance of origin P0
hole "HOLE - FRONT STILE BOLT CLEARANCE 1" at (1224, -642.74, 332.26) direction (0, 1, 0) diameter 7 depth 1.2 tip angle 118 bodies 3 in component "211102 WALL - PANEL FRAME - SIDE LOWER - RH"
ref_plane "WorkPlane21" through (0, -622.74, 0) normal (0, 1, 0) x (0, 0, 1) in component "211102 WALL - PANEL FRAME - SIDE LOWER - RH"
sketch "HOLE CENTRE - FRONT STILE KEY ACCESS 1" plane through (0, -622.74, 0) normal (0, 1, 0) x (1, 0, 0) in component "211102 WALL - PANEL FRAME - SIDE LOWER - RH"
  point P0 (1224, -332.26)
  dimension "d422" = 1224
  dimension "d423" = 332.26
  measures "d422" horizontal distance of origin P0
  measures "d423" vertical distance of origin P0
hole "HOLE - FRONT STILE KEY ACCESS 1" at (1224, -622.74, 332.26) direction (0, -1, 0) diameter 19 depth 1.2 tip angle 118 bodies 3 in component "211102 WALL - PANEL FRAME - SIDE LOWER - RH"
pattern_linear "PATTERN - FRONT STILE BOLT HOLES" count 3 spacing 351.37 along (0, 0, 1) of "HOLE - FRONT STILE BOLT CLEARANCE 1", "HOLE - FRONT STILE KEY ACCESS 1" in component "211102 WALL - PANEL FRAME - SIDE LOWER - RH"
ref_plane "WorkPlane22" through (1204, 0, 0) normal (1, 0, 0) x (0, 1, 0) in component "211102 WALL - PANEL FRAME - SIDE LOWER - RH"
sketch "HOLE CENTRE - BACK STILE CORNER RIVNUT 1" plane through (1204, 0, 0) normal (1, 0, 0) x (0, 0, -1) in component "211102 WALL - PANEL FRAME - SIDE LOWER - RH"
  point P0 (-332.26, 824)
  dimension "d433" = 824
  dimension "d434" = 332.26
  measures "d433" vertical distance of origin P0
  measures "d434" horizontal distance of origin P0
hole "HOLE - BACK STILE CORNER RIVNUT 1" at (1204, 824, 332.26) direction (1, 0, 0) diameter 9.53 depth 1.2 tip angle 118 bodies 4 in component "211102 WALL - PANEL FRAME - SIDE LOWER - RH"
pattern_linear "PATTERN - BACK STILE CORNER RIVNUTS" count 3 spacing 339.305 along (0, 0, 1) of "HOLE - BACK STILE CORNER RIVNUT 1" in component "211102 WALL - PANEL FRAME - SIDE LOWER - RH"
ref_plane "WorkPlane1" through (0, 0, 1255) normal (0, 0, 1) x (1, 0, 0) in component "831002 HARDWARE - STOP WASHER - Ø10.5 X Ø20 X 1.5 - AL"
sketch "SKETCH - STOP WASHER TOP RAIL" plane through (0, 0, 1255) normal (0, 0, 1) x (1, 0, 0) in component "831002 HARDWARE - STOP WASHER - Ø10.5 X Ø20 X 1.5 - AL"
  circle A0 centre (1224, -422.74) radius 10
  circle A1 centre (1224, -422.74) radius 5.25
  dimension "d444" = 1224
  dimension "d445" = 422.74
  dimension "d446" = 20
  dimension "d447" = 10.5
  measures "d444" horizontal distance of origin A0.centre
  measures "d445" vertical distance of origin A0.centre
  measures "d446" diameter of A0
  measures "d447" diameter of A1
extrude "EXTRUDE - STOP WASHER TOP RAIL" add sketch "SKETCH - STOP WASHER TOP RAIL" along normal blind 1.5 separate body makes body 13 in component "831002 HARDWARE - STOP WASHER - Ø10.5 X Ø20 X 1.5 - AL"
ref_plane "WorkPlane1" through (0, 0, 1256.5) normal (0, 0, 1) x (1, 0, 0) in component "838003 HARDWARE - RIVET NUT - M6 - SHEREX CAH3-610-4.2"
sketch "SKETCH - RIVNUT HEAD TOP RAIL" plane through (0, 0, 1256.5) normal (0, 0, 1) x (1, 0, 0) in component "838003 HARDWARE - RIVET NUT - M6 - SHEREX CAH3-610-4.2"
  circle A0 centre (1224, -422.74) radius 6.48
  circle A1 centre (1224, -422.74) radius 3
  dimension "d452" = 1224
  dimension "d453" = 422.74
  dimension "d454" = 12.96
  dimension "d455" = 6
  measures "d452" horizontal distance of origin A0.centre
  measures "d453" vertical distance of origin A0.centre
  measures "d454" diameter of A0
  measures "d455" diameter of A1
extrude "EXTRUDE - RIVNUT HEAD TOP RAIL" add sketch "SKETCH - RIVNUT HEAD TOP RAIL" along normal blind 0.76 separate body makes body 14 in component "838003 HARDWARE - RIVET NUT - M6 - SHEREX CAH3-610-4.2"
ref_plane "WorkPlane2" through (0, 0, 1256.5) normal (0, 0, 1) x (1, 0, 0) in component "838003 HARDWARE - RIVET NUT - M6 - SHEREX CAH3-610-4.2"
sketch "SKETCH - RIVNUT BODY TOP RAIL" plane through (0, 0, 1256.5) normal (0, 0, 1) x (1, 0, 0) in component "838003 HARDWARE - RIVET NUT - M6 - SHEREX CAH3-610-4.2"
  circle A0 centre (1224, -422.74) radius 4.75
  circle A1 centre (1224, -422.74) radius 3
  dimension "d460" = 1224
  dimension "d461" = 422.74
  dimension "d462" = 9.5
  dimension "d463" = 6
  measures "d460" horizontal distance of origin A0.centre
  measures "d461" vertical distance of origin A0.centre
  measures "d462" diameter of A0
  measures "d463" diameter of A1
extrude "EXTRUDE - RIVNUT BODY TOP RAIL" add sketch "SKETCH - RIVNUT BODY TOP RAIL" against normal blind 10.16 separate body makes body 15 in component "838003 HARDWARE - RIVET NUT - M6 - SHEREX CAH3-610-4.2"
combine "COMBINE - RIVNUT TOP RAIL" operation add target body 14 tool bodies 15 in component "838003 HARDWARE - RIVET NUT - M6 - SHEREX CAH3-610-4.2"
pattern_linear "PATTERN - STOP WASHER - TOP RAIL" count 4 spacing 350.9133 along (0, 1, 0) of bodies 13 makes body 16 at (1222.6198, -80.1066, 1255) makes body 17 at (1222.6198, 270.8068, 1255) makes body 18 at (1225.3802, 638.2799, 1255) in component "831002 HARDWARE - STOP WASHER - Ø10.5 X Ø20 X 1.5 - AL"
pattern_linear "PATTERN - RIVNUT - TOP RAIL" count 4 spacing 350.9133 along (0, 1, 0) of bodies 14 makes body 19 at (1226.167, -67.5998, 1249.7267) makes body 20 at (1226.167, 283.3136, 1249.7267) makes body 21 at (1226.167, 634.2269, 1249.7267) in component "838003 HARDWARE - RIVET NUT - M6 - SHEREX CAH3-610-4.2"
ref_plane "WorkPlane3" through (0, 0, 1255) normal (0, 0, 1) x (1, 0, 0) in component "838003 HARDWARE - RIVET NUT - M6 - SHEREX CAH3-610-4.2"
sketch "SKETCH - RIVNUT HEAD TOP RAIL SPIGOT FRONT" plane through (0, 0, 1255) normal (0, 0, 1) x (1, 0, 0) in component "838003 HARDWARE - RIVET NUT - M6 - SHEREX CAH3-610-4.2"
  circle A0 centre (1224, -542.74) radius 6.48
  circle A1 centre (1224, -542.74) radius 3
  dimension "d478" = 1224
  dimension "d479" = 542.74
  dimension "d480" = 12.96
  dimension "d481" = 6
  measures "d478" horizontal distance of origin A0.centre
  measures "d479" vertical distance of origin A0.centre
  measures "d480" diameter of A0
  measures "d481" diameter of A1
extrude "EXTRUDE - RIVNUT HEAD TOP RAIL SPIGOT FRONT" add sketch "SKETCH - RIVNUT HEAD TOP RAIL SPIGOT FRONT" along normal blind 0.76 separate body makes body 22 in component "838003 HARDWARE - RIVET NUT - M6 - SHEREX CAH3-610-4.2"
ref_plane "WorkPlane4" through (0, 0, 1255) normal (0, 0, 1) x (1, 0, 0) in component "838003 HARDWARE - RIVET NUT - M6 - SHEREX CAH3-610-4.2"
sketch "SKETCH - RIVNUT BODY TOP RAIL SPIGOT FRONT" plane through (0, 0, 1255) normal (0, 0, 1) x (1, 0, 0) in component "838003 HARDWARE - RIVET NUT - M6 - SHEREX CAH3-610-4.2"
  circle A0 centre (1224, -542.74) radius 4.75
  circle A1 centre (1224, -542.74) radius 3
  dimension "d486" = 1224
  dimension "d487" = 542.74
  dimension "d488" = 9.5
  dimension "d489" = 6
  measures "d486" horizontal distance of origin A0.centre
  measures "d487" vertical distance of origin A0.centre
  measures "d488" diameter of A0
  measures "d489" diameter of A1
extrude "EXTRUDE - RIVNUT BODY TOP RAIL SPIGOT FRONT" add sketch "SKETCH - RIVNUT BODY TOP RAIL SPIGOT FRONT" against normal blind 10.16 separate body makes body 23 in component "838003 HARDWARE - RIVET NUT - M6 - SHEREX CAH3-610-4.2"
combine "COMBINE - RIVNUT TOP RAIL SPIGOT FRONT" operation add target body 22 tool bodies 23 in component "838003 HARDWARE - RIVET NUT - M6 - SHEREX CAH3-610-4.2"
ref_plane "WorkPlane1" through (0, 0, 1255.76) normal (0, 0, 1) x (1, 0, 0) in component "831001 HARDWARE - LOCATING SPIGOT - M6 X Ø8 - STAINLESS"
sketch "SKETCH - SPIGOT PIN TOP RAIL SPIGOT FRONT" plane through (0, 0, 1255.76) normal (0, 0, 1) x (1, 0, 0) in component "831001 HARDWARE - LOCATING SPIGOT - M6 X Ø8 - STAINLESS"
  circle A0 centre (1224, -542.74) radius 4
  dimension "d496" = 1224
  dimension "d497" = 542.74
  dimension "d498" = 8
  measures "d496" horizontal distance of origin A0.centre
  measures "d497" vertical distance of origin A0.centre
  measures "d498" diameter of A0
extrude "EXTRUDE - SPIGOT PIN TOP RAIL SPIGOT FRONT" add sketch "SKETCH - SPIGOT PIN TOP RAIL SPIGOT FRONT" along normal blind 7.24 separate body makes body 24 in component "831001 HARDWARE - LOCATING SPIGOT - M6 X Ø8 - STAINLESS"
ref_plane "WorkPlane2" through (0, 0, 1255.76) normal (0, 0, 1) x (1, 0, 0) in component "831001 HARDWARE - LOCATING SPIGOT - M6 X Ø8 - STAINLESS"
sketch "SKETCH - SPIGOT THREAD TOP RAIL SPIGOT FRONT" plane through (0, 0, 1255.76) normal (0, 0, 1) x (1, 0, 0) in component "831001 HARDWARE - LOCATING SPIGOT - M6 X Ø8 - STAINLESS"
  circle A0 centre (1224, -542.74) radius 3
  dimension "d503" = 1224
  dimension "d504" = 542.74
  dimension "d505" = 6
  measures "d503" horizontal distance of origin A0.centre
  measures "d504" vertical distance of origin A0.centre
  measures "d505" diameter of A0
extrude "EXTRUDE - SPIGOT THREAD TOP RAIL SPIGOT FRONT" add sketch "SKETCH - SPIGOT THREAD TOP RAIL SPIGOT FRONT" against normal blind 10 separate body makes body 25 in component "831001 HARDWARE - LOCATING SPIGOT - M6 X Ø8 - STAINLESS"
combine "COMBINE - SPIGOT TOP RAIL SPIGOT FRONT" operation add target body 24 tool bodies 25 in component "831001 HARDWARE - LOCATING SPIGOT - M6 X Ø8 - STAINLESS"
ref_plane "WorkPlane5" through (0, 0, 1255) normal (0, 0, 1) x (1, 0, 0) in component "838003 HARDWARE - RIVET NUT - M6 - SHEREX CAH3-610-4.2"
sketch "SKETCH - RIVNUT HEAD TOP RAIL SPIGOT BACK" plane through (0, 0, 1255) normal (0, 0, 1) x (1, 0, 0) in component "838003 HARDWARE - RIVET NUT - M6 - SHEREX CAH3-610-4.2"
  circle A0 centre (1224, 750) radius 6.48
  circle A1 centre (1224, 750) radius 3
  dimension "d512" = 1224
  dimension "d513" = 750
  dimension "d514" = 12.96
  dimension "d515" = 6
  measures "d512" horizontal distance of origin A0.centre
  measures "d513" vertical distance of origin A0.centre
  measures "d514" diameter of A0
  measures "d515" diameter of A1
extrude "EXTRUDE - RIVNUT HEAD TOP RAIL SPIGOT BACK" add sketch "SKETCH - RIVNUT HEAD TOP RAIL SPIGOT BACK" along normal blind 0.76 separate body makes body 26 in component "838003 HARDWARE - RIVET NUT - M6 - SHEREX CAH3-610-4.2"
ref_plane "WorkPlane6" through (0, 0, 1255) normal (0, 0, 1) x (1, 0, 0) in component "838003 HARDWARE - RIVET NUT - M6 - SHEREX CAH3-610-4.2"
sketch "SKETCH - RIVNUT BODY TOP RAIL SPIGOT BACK" plane through (0, 0, 1255) normal (0, 0, 1) x (1, 0, 0) in component "838003 HARDWARE - RIVET NUT - M6 - SHEREX CAH3-610-4.2"
  circle A0 centre (1224, 750) radius 4.75
  circle A1 centre (1224, 750) radius 3
  dimension "d520" = 1224
  dimension "d521" = 750
  dimension "d522" = 9.5
  dimension "d523" = 6
  measures "d520" horizontal distance of origin A0.centre
  measures "d521" vertical distance of origin A0.centre
  measures "d522" diameter of A0
  measures "d523" diameter of A1
extrude "EXTRUDE - RIVNUT BODY TOP RAIL SPIGOT BACK" add sketch "SKETCH - RIVNUT BODY TOP RAIL SPIGOT BACK" against normal blind 10.16 separate body makes body 27 in component "838003 HARDWARE - RIVET NUT - M6 - SHEREX CAH3-610-4.2"
combine "COMBINE - RIVNUT TOP RAIL SPIGOT BACK" operation add target body 26 tool bodies 27 in component "838003 HARDWARE - RIVET NUT - M6 - SHEREX CAH3-610-4.2"
ref_plane "WorkPlane3" through (0, 0, 1255.76) normal (0, 0, 1) x (1, 0, 0) in component "831001 HARDWARE - LOCATING SPIGOT - M6 X Ø8 - STAINLESS"
sketch "SKETCH - SPIGOT PIN TOP RAIL SPIGOT BACK" plane through (0, 0, 1255.76) normal (0, 0, 1) x (1, 0, 0) in component "831001 HARDWARE - LOCATING SPIGOT - M6 X Ø8 - STAINLESS"
  circle A0 centre (1224, 750) radius 4
  dimension "d530" = 1224
  dimension "d531" = 750
  dimension "d532" = 8
  measures "d530" horizontal distance of origin A0.centre
  measures "d531" vertical distance of origin A0.centre
  measures "d532" diameter of A0
extrude "EXTRUDE - SPIGOT PIN TOP RAIL SPIGOT BACK" add sketch "SKETCH - SPIGOT PIN TOP RAIL SPIGOT BACK" along normal blind 7.24 separate body makes body 28 in component "831001 HARDWARE - LOCATING SPIGOT - M6 X Ø8 - STAINLESS"
ref_plane "WorkPlane4" through (0, 0, 1255.76) normal (0, 0, 1) x (1, 0, 0) in component "831001 HARDWARE - LOCATING SPIGOT - M6 X Ø8 - STAINLESS"
sketch "SKETCH - SPIGOT THREAD TOP RAIL SPIGOT BACK" plane through (0, 0, 1255.76) normal (0, 0, 1) x (1, 0, 0) in component "831001 HARDWARE - LOCATING SPIGOT - M6 X Ø8 - STAINLESS"
  circle A0 centre (1224, 750) radius 3
  dimension "d537" = 1224
  dimension "d538" = 750
  dimension "d539" = 6
  measures "d537" horizontal distance of origin A0.centre
  measures "d538" vertical distance of origin A0.centre
  measures "d539" diameter of A0
extrude "EXTRUDE - SPIGOT THREAD TOP RAIL SPIGOT BACK" add sketch "SKETCH - SPIGOT THREAD TOP RAIL SPIGOT BACK" against normal blind 10 separate body makes body 29 in component "831001 HARDWARE - LOCATING SPIGOT - M6 X Ø8 - STAINLESS"
combine "COMBINE - SPIGOT TOP RAIL SPIGOT BACK" operation add target body 28 tool bodies 29 in component "831001 HARDWARE - LOCATING SPIGOT - M6 X Ø8 - STAINLESS"
ref_plane "WorkPlane2" through (1204, 0, 0) normal (1, 0, 0) x (0, 1, 0) in component "831002 HARDWARE - STOP WASHER - Ø10.5 X Ø20 X 1.5 - AL"
sketch "SKETCH - STOP WASHER BACK STILE CORNER" plane through (1204, 0, 0) normal (1, 0, 0) x (0, 0, -1) in component "831002 HARDWARE - STOP WASHER - Ø10.5 X Ø20 X 1.5 - AL"
  circle A0 centre (-332.26, 824) radius 10
  circle A1 centre (-332.26, 824) radius 5.25
  dimension "d546" = 824
  dimension "d547" = 332.26
  dimension "d548" = 20
  dimension "d549" = 10.5
  measures "d546" vertical distance of origin A0.centre
  measures "d547" horizontal distance of origin A0.centre
  measures "d548" diameter of A0
  measures "d549" diameter of A1
extrude "EXTRUDE - STOP WASHER BACK STILE CORNER" add sketch "SKETCH - STOP WASHER BACK STILE CORNER" against normal blind 1.5 separate body makes body 30 in component "831002 HARDWARE - STOP WASHER - Ø10.5 X Ø20 X 1.5 - AL"
ref_plane "WorkPlane7" through (1202.5, 0, 0) normal (1, 0, 0) x (0, 1, 0) in component "838003 HARDWARE - RIVET NUT - M6 - SHEREX CAH3-610-4.2"
sketch "SKETCH - RIVNUT HEAD BACK STILE CORNER" plane through (1202.5, 0, 0) normal (1, 0, 0) x (0, 0, -1) in component "838003 HARDWARE - RIVET NUT - M6 - SHEREX CAH3-610-4.2"
  circle A0 centre (-332.26, 824) radius 6.48
  circle A1 centre (-332.26, 824) radius 3
  dimension "d556" = 824
  dimension "d557" = 332.26
  dimension "d558" = 12.96
  dimension "d559" = 6
  measures "d556" vertical distance of origin A0.centre
  measures "d557" horizontal distance of origin A0.centre
  measures "d558" diameter of A0
  measures "d559" diameter of A1
extrude "EXTRUDE - RIVNUT HEAD BACK STILE CORNER" add sketch "SKETCH - RIVNUT HEAD BACK STILE CORNER" against normal blind 0.76 separate body makes body 31 in component "838003 HARDWARE - RIVET NUT - M6 - SHEREX CAH3-610-4.2"
ref_plane "WorkPlane8" through (1202.5, 0, 0) normal (1, 0, 0) x (0, 1, 0) in component "838003 HARDWARE - RIVET NUT - M6 - SHEREX CAH3-610-4.2"
sketch "SKETCH - RIVNUT BODY BACK STILE CORNER" plane through (1202.5, 0, 0) normal (1, 0, 0) x (0, 0, -1) in component "838003 HARDWARE - RIVET NUT - M6 - SHEREX CAH3-610-4.2"
  circle A0 centre (-332.26, 824) radius 4.75
  circle A1 centre (-332.26, 824) radius 3
  dimension "d566" = 824
  dimension "d567" = 332.26
  dimension "d568" = 9.5
  dimension "d569" = 6
  measures "d566" vertical distance of origin A0.centre
  measures "d567" horizontal distance of origin A0.centre
  measures "d568" diameter of A0
  measures "d569" diameter of A1
extrude "EXTRUDE - RIVNUT BODY BACK STILE CORNER" add sketch "SKETCH - RIVNUT BODY BACK STILE CORNER" along normal blind 10.16 separate body makes body 32 in component "838003 HARDWARE - RIVET NUT - M6 - SHEREX CAH3-610-4.2"
combine "COMBINE - RIVNUT BACK STILE CORNER" operation add target body 31 tool bodies 32 in component "838003 HARDWARE - RIVET NUT - M6 - SHEREX CAH3-610-4.2"
pattern_linear "PATTERN - STOP WASHER - BACK STILE CORNER" count 3 spacing 339.305 along (0, 0, 1) of bodies 30 makes body 33 at (1204, 815.9412, 673.914) makes body 34 at (1204, 815.9412, 1013.219) in component "831002 HARDWARE - STOP WASHER - Ø10.5 X Ø20 X 1.5 - AL"
pattern_linear "PATTERN - RIVNUT - BACK STILE CORNER" count 3 spacing 339.305 along (0, 0, 1) of bodies 31 makes body 35 at (1209.2733, 828.6778, 670.7402) makes body 36 at (1209.2733, 828.6778, 1010.0452) in component "838003 HARDWARE - RIVET NUT - M6 - SHEREX CAH3-610-4.2"
component "211102 WALL - PANEL FRAME - SIDE LOWER - RH" placed x (1, 0, 0) y (0, 1, 0) z (0, 0, 1) at (0, 0, 0)
component "211302 WALL - SKIN - SIDE LOWER - RH" placed x (1, 0, 0) y (0, 1, 0) z (0, 0, 1) at (0, 0, 0)
component "211502 WALL - CAVITY FILL - SIDE LOWER - RH" placed x (1, 0, 0) y (0, 1, 0) z (0, 0, 1) at (0, 0, 0)
component "831002 HARDWARE - STOP WASHER - Ø10.5 X Ø20 X 1.5 - AL" placed x (1, 0, 0) y (0, 1, 0) z (0, 0, 1) at (0, 0, 0)
component "838003 HARDWARE - RIVET NUT - M6 - SHEREX CAH3-610-4.2" placed x (1, 0, 0) y (0, 1, 0) z (0, 0, 1) at (0, 0, 0)
component "831001 HARDWARE - LOCATING SPIGOT - M6 X Ø8 - STAINLESS" placed x (1, 0, 0) y (0, 1, 0) z (0, 0, 1) at (0, 0, 0)
equation "pod_w_Ref = 2500 mm" comment "DECIDED: D-01; conventions s4 (X = +-1250)"
equation "pod_d_Ref = 1700 mm" comment "DECIDED: D-01; conventions s4 (Y = +-850)"
equation "pod_h_Ref = 2400 mm" comment "DECIDED: D-21 (room floor to roof skin top)"
equation "glide_h_Ref = 10 mm" comment "ASSUMPTION: layout study inputs.py glide_h"
equation "band_h_Ref = 100 mm" comment "SOURCE: layout study B1 list B-BAND 100x40; inputs.py base_h"
equation "outer_t_Ref = skin_t_Ref + bond_t_Ref + frame_t_Ref" comment "DECIDED: PM ruling 2026-10-31: ACP 3 + bond line 3 + frame 40, walls and ceiling (was 43)"
equation "cav_gap_Ref = 4 mm" comment "DECIDED: D-16, D-42: the gap between the outer panel and the lining cassette in the wall and ceiling stack"
equation "cass_t_Ref = 34 mm" comment "SOURCE: layout study B1 final list L-CASS 34 (tray + 25 gap + felt 9)"
equation "stack_t_Ref = outer_t_Ref + cav_gap_Ref + cass_t_Ref" comment "CALCULATION: D-16, D-42 stack, walls and ceiling: outer panel + cavity gap + cassette (PM ruling 2026-10-31 on outer_t)"
equation "wall_depth_Ref = 1495 mm" comment "DECIDED: PM ruling pass C: side walls start at the decor back plate (Y -645), as v1 (1496)"